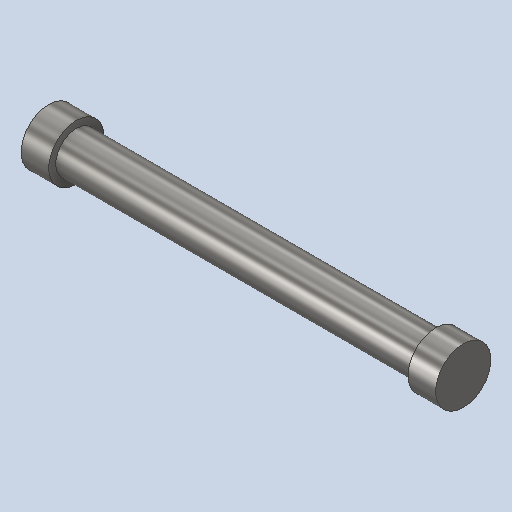
# Autodesk Inventor part: 9
Saved by Autodesk Inventor 2027.1 (Build 311270010, 270A)
## iProperties
Part Number: 9
Material: Allgemein
Document SubType Name: Modellieren
Designer: Asus
Appearance: Halbpoliert
Author: Asus
Autodesk Inventor part; units mm, degrees
ref_plane "YZ-Ebene" through (0, 0, 0) normal (1, 0, 0) x (0, 1, 0)
ref_plane "XZ-Ebene" through (0, 0, 0) normal (0, 1, 0) x (-1, 0, 0)
ref_plane "XY-Ebene" through (0, 0, 0) normal (0, 0, 1) x (1, 0, 0)
sketch "Skizze1" plane through (0, 0, 0) normal (0, 0, 1) x (1, 0, 0)
  line L0 (-15, 0) -> (15, 0)
  line L1 (-15, 0) -> (-15, 2)
  line L2 (-15, 2) -> (-13, 2)
  line L3 (-13, 2) -> (-13, 1.5)
  line L4 (0, 2.4) -> (0, -0.4) construction
  line L5 (15, 0) -> (15, 2)
  line L6 (15, 2) -> (13, 2)
  line L7 (13, 2) -> (13, 1.5)
  line L8 (-13, 1.5) -> (13, 1.5)
  point P0 (0, 0)
  point P1 (0, 0)
  dimension "d0" = 30
  dimension "d1" = 2
  dimension "d2" = 2
  dimension "d3" = 1.5
  constraints: 16 end point, 3 symmetric about line, 2 horizontal, 2 perpendicular, 1 coincident, 1 midpoint, 1 vertical
  measures "d0" distance of L0.start L0.end
  measures "d1" distance of L1.end L2.end
  measures "d2" distance of L0.start L1.end
  measures "d3" distance between parallel lines of L0 L8
revolve "Umdrehung1" add sketch "Skizze1" angle 360 about axis through (-15, 0, 0) along (1, 0, 0)
